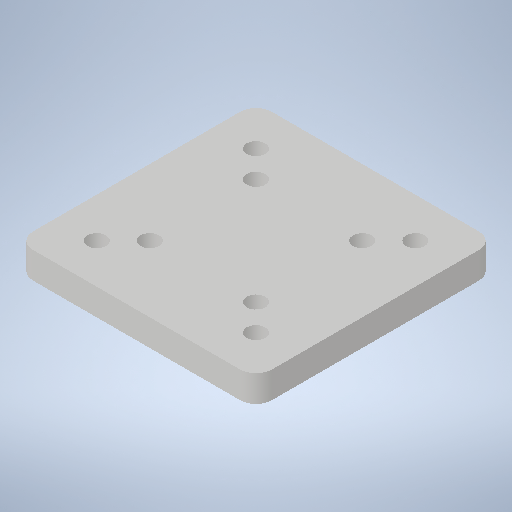
# Autodesk Inventor part: FC Mount
Saved by Autodesk Inventor 2025.2 (Build 292293000, 293)
## iProperties
Created: 2026-05-19
Part Number: FC Mount
Material: Generic
Document SubType Name: Modeling
Designer: crazi
Density: 1 g/cm^3
Appearance: Default
Author: crazi
Autodesk Inventor part; units mm, degrees
ref_plane "YZ Plane" through (0, 0, 0) normal (1, 0, 0) x (0, 1, 0)
ref_plane "XZ Plane" through (0, 0, 0) normal (0, 1, 0) x (-1, 0, 0)
ref_plane "XY Plane" through (0, 0, 0) normal (0, 0, 1) x (1, 0, 0)
sketch "Sketch1" plane through (0, 0, 0) normal (0, 1, 0) x (-1, 0, 0)
  circle A0 centre (-10.2011, -10.3829) radius 1.75
  circle A1 centre (-15.201, -15.3829) radius 1.75
  circle A2 centre (9.7989, -10.3829) radius 1.75
  circle A3 centre (14.7988, -15.3829) radius 1.75
  circle A4 centre (-10.2011, 9.6101) radius 1.75
  circle A5 centre (-15.201, 14.6101) radius 1.75
  circle A6 centre (9.7989, 9.6101) radius 1.75
  circle A7 centre (14.7988, 14.6101) radius 1.75
  line L0 (-22.701, 22.1101) -> (-22.701, -22.8829)
  line L1 (-22.701, -22.8829) -> (22.2988, -22.8829)
  line L2 (22.2988, -22.8829) -> (22.2988, 22.1101)
  line L3 (22.2988, 22.1101) -> (-22.701, 22.1101)
  point P0 (0, 0)
  constraints: 8 centre point, 8 end point, 3 perpendicular
extrude "Extrusion1" add sketch "Sketch1" along normal blind 5
chamfer "Chamfer1" distance 1.6 angle 45 4 edges at (16.951, 0, 14.6101) (-13.0488, 0, 14.6101) (-13.0488, 0, -15.3829) (16.951, 0, -15.3829)
fillet "Fillet1" radius 3 4 edges at (-22.2988, 2.5, -22.8829) (-22.2988, 2.5, 22.1101) (22.701, 2.5, 22.1101) (22.701, 2.5, -22.8829)
body "Solid1"
